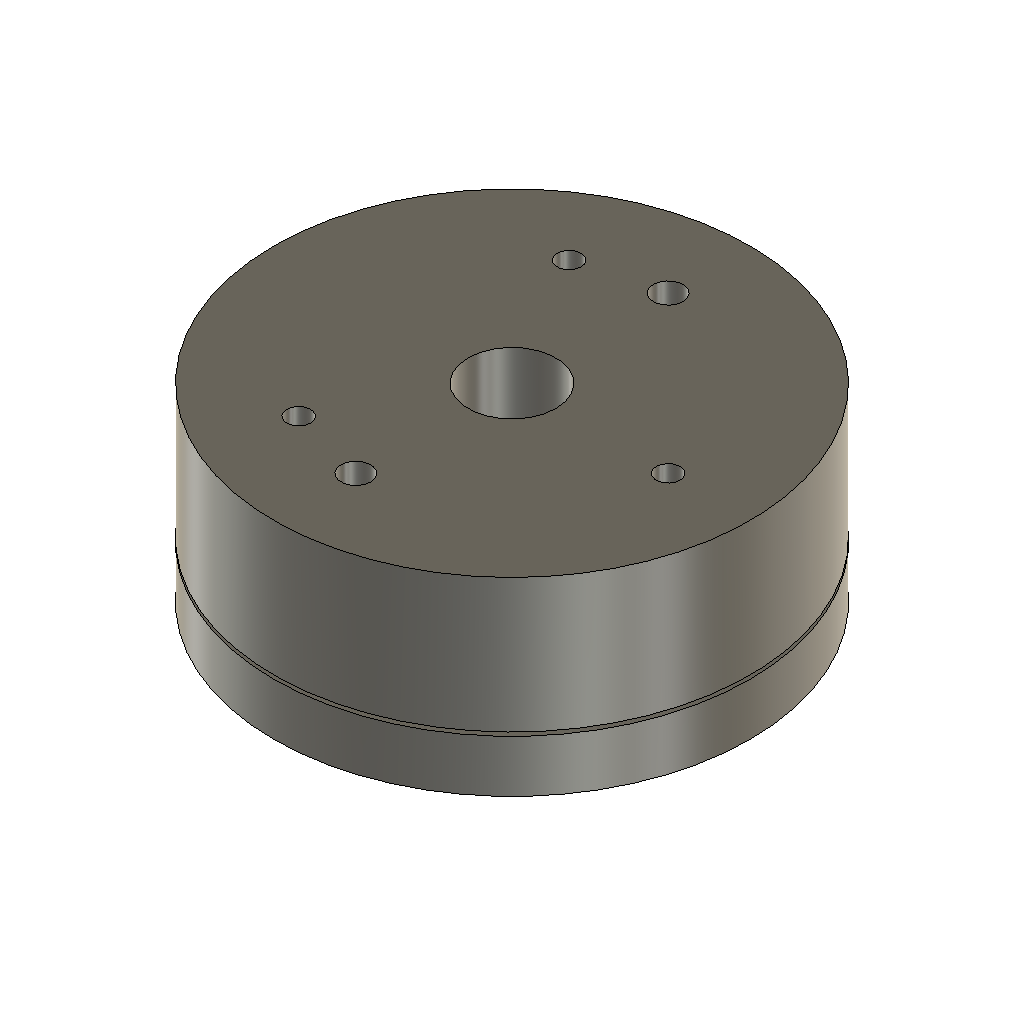
SmartKnob Enclosure (Autodesk Fusion 360 archive; units mm, degrees)
design "BLDCMotor v1"
Autodesk Fusion 360 part; units mm, degrees
sketch "BottomStator" plane through (0, 0, 0) normal (0, 0, 1) x (1, 0, 0)
  circle A0 centre (10.2509, 0) radius 0.8
  circle A1 centre (-5.1254, 8.8775) radius 0.8
  line L0 (-12.3, 4) -> (-9, 4)
  line L1 (-12.3, -4) -> (-12.3, 4)
  circle A2 centre (0, 0) radius 5.75
  line L2 (0, 0) -> (-5.1254, -8.8775) construction
  line L3 (-9, 4) -> (-9, -4)
  line L4 (0, 0) -> (-5.1254, 8.8775) construction
  circle A3 centre (-5.1254, -8.8775) radius 0.8
  line L5 (10.2509, 0) -> (0, 0) construction
  line L6 (-5.1254, -8.8775) -> (-5.1254, 8.8775) construction
  circle A4 centre (0, 0) radius 16
  line L7 (10.2509, 0) -> (-5.1254, -8.8775) construction
  line L8 (-5.1254, 8.8775) -> (10.2509, 0) construction
  circle A5 centre (0, 0) radius 2.95
  line L9 (-9, -4) -> (-12.3, -4)
  point P0 (-9, 0)
  dimension "d1" = 1.6
  dimension "d2" = 1.6
  dimension "d3" = 1.6
  dimension "d4" = 17.755
  dimension "d5" = 11.5
  dimension "d11" = 32
  dimension "d21" = 8
  dimension "d22" = 9
  dimension "d23" = 5.9
  dimension "d18" = 3.3
  dimension "d36" = 10.2509
  constraint coincident A0.centre L5.start
  constraint coincident L2.end A3.centre
  constraint coincident A1.centre L4.end
  constraint coincident A2.centre L2.start
  constraint equal L2 L5
  constraint equal L2 L4
  constraint equal L6 L7
  constraint equal L7 L8
  constraint horizontal L5
  constraint horizontal L0
  constraint vertical L3
  constraint horizontal L9
  constraint vertical L1
  constraint midpoint P0 L3
  constraint coincident P0 L5
  measures "d1" diameter of A0
  measures "d2" diameter of A3
  measures "d3" diameter of A1
  measures "d4" distance of A0.centre L2.end
  measures "d5" diameter of A2
  measures "d11" diameter of A4
  measures "d21" distance of L0.start L1.start
  measures "d22" distance of P0 A2.centre
  measures "d23" diameter of A5
  measures "d18" distance of L0.start L0.end
  measures "d36" distance of A0.centre A2.centre
sketch "TopRotor" plane through (0, 0, 0) normal (0, 0, 1) x (1, 0, 0)
  line L0 (-5.25, 9.0933) -> (10.5, 0) construction
  line L1 (10.5, 0) -> (-5.25, -9.0933) construction
  line L2 (-5.25, -9.0933) -> (-5.25, 9.0933) construction
  line L3 (-5.25, 9.0933) -> (0, 0) construction
  line L4 (0, 0) -> (10.5, 0) construction
  line L5 (0, 0) -> (-5.25, -9.0933) construction
  circle A0 centre (-5.25, 9.0933) radius 0.8
  circle A1 centre (10.5, 0) radius 0.8
  circle A2 centre (-5.25, -9.0933) radius 0.8
  line L6 (0, 10.5) -> (0, -10.5) construction
  circle A3 centre (0, 10.5) radius 1
  circle A4 centre (0, -10.5) radius 1
  circle A5 centre (0, 0) radius 16
  circle A6 centre (0, 0) radius 5.75
  circle A7 centre (0, 0) radius 2.95
  dimension "d32" = 10.5
  dimension "d33" = 1.6
  dimension "d34" = 1.6
  dimension "d35" = 1.6
  dimension "d37" = 18.1865
  dimension "d38" = 21
  dimension "d39" = 2
  dimension "d40" = 2
  dimension "d43" = 32
  dimension "d45" = 11.5
  dimension "d53" = 5.9
  constraint vertical L2
  constraint equal L0 L2
  constraint equal L0 L1
  constraint equal L3 L4
  constraint equal L4 L5
  constraint coincident L3.end L4.start
  constraint coincident L0.start L2.end
  constraint coincident L0.end L1.start
  constraint coincident L1.end L2.start
  constraint vertical L6
  constraint midpoint L6 L3.end
  constraint coincident L6.start A3.centre
  constraint coincident L6.end A4.centre
  constraint concentric A5 A6
  constraint concentric A6 A7
  measures "d32" distance of L0.end L3.end
  measures "d33" diameter of A0
  measures "d34" diameter of A1
  measures "d35" diameter of A2
  measures "d37" distance of L0.start L0.end
  measures "d38" distance of L6.start L6.end
  measures "d39" diameter of A3
  measures "d40" diameter of A4
  measures "d43" diameter of A5
  measures "d45" diameter of A6
  measures "d53" diameter of A7
extrude "Extrude1" add sketch "BottomStator" along normal blind 3.5 contours A4 makes body 1 in component "Stator"
extrude "Extrude1'" add sketch "TopRotor" against normal blind 9 from surface at 12.75 separate body contours A5 makes body 2 in component "Rotor"
extrude "Extrude2" add sketch "TopRotor" against normal blind 15 from surface at 12.75 contours A6 bodies 2 in component "Rotor"
component "Stator" placed x (1, 0, 0) y (0, 1, 0) z (0, 0, 1) at (0, 0, 0)
component "Rotor" placed x (1, 0, 0) y (0, 1, 0) z (0, 0, 1) at (0, 0, 0)
equation "d2 = d1"
equation "d3 = d1"
equation "d5 = magnet_diameter"
equation "d11 = diameter"
equation "d23 = inner_diameter"
equation "d28 = 3 mm"
equation "d29 = d28"
equation "d30 = d28"
equation "d32 = ( 21 / 2 ) * 1 mm"
equation "d34 = d33"
equation "d35 = d33"
equation "d40 = d39"
equation "height = 12.75 mm"
equation "diameter = 32 mm"
equation "d43 = diameter"
equation "magnet_diameter = 11.5 mm"
equation "d45 = magnet_diameter"
equation "d46 = height"
equation "d49 = height"
equation "inner_diameter = 5.9 mm"
equation "d53 = inner_diameter"

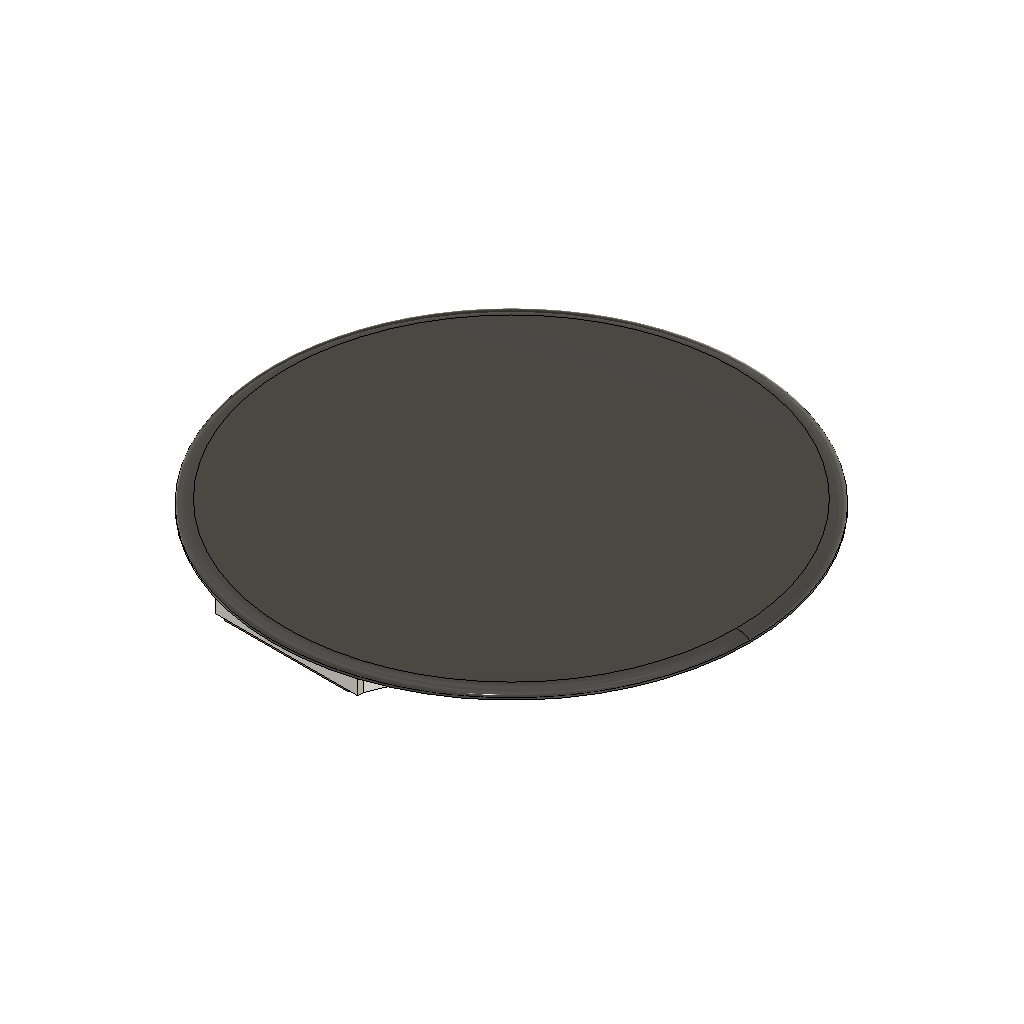
design "Display"
Autodesk Fusion 360 part; units mm, degrees
sketch "Sketch1" plane through (0, 0, 0) normal (0, 0, 1) x (1, 0, 0)
  circle A0 centre (0, 0) radius 16.2
  circle A1 centre (0, 0) radius 17.37 construction
  circle A2 centre (0, 0) radius 17.6 construction
  circle A3 centre (0, 0) radius 17.8
  line L0 (0, 0) -> (0, -34.4204) construction
  line L1 (-6.6, -20.3) -> (6.6, -20.3)
  line L2 (8.5, -15.6394) -> (-8.5, -15.6394) construction
  line L3 (6.6, -20.3) -> (8.5, -15.6394)
  line L4 (-6.6, -20.3) -> (-8.5, -15.6394)
  line L5 (-6.6, -20.3) -> (-6.6, -20.8)
  line L6 (-6.6, -20.8) -> (6.6, -20.8)
  line L7 (6.6, -20.8) -> (6.6, -20.3)
  circle A4 centre (0, 0) radius 22.5 construction
  line L8 (-5.7, -20.8) -> (5.7, -20.8)
  line L9 (5.7, -20.8) -> (5.7, -10.06)
  line L10 (5.7, -10.06) -> (-5.7, -10.06)
  line L11 (-5.7, -10.06) -> (-5.7, -20.8)
  point P0 (0, -20.3)
  dimension "d1" = 32.4
  dimension "d2" = 34.74
  dimension "d3" = 35.2
  dimension "d4" = 35.6
  dimension "d5" = 13.2
  dimension "d6" = 20.3
  dimension "d7" = 17
  dimension "d8" = 0.5
  dimension "d9" = 21.822
  dimension "d10" = 45
  dimension "d11" = 0.678
  dimension "d24" = 11.4
  dimension "d25" = 10.24
  constraint coincident A0.centre A1.centre
  constraint concentric A0 A1
  constraint concentric A1 A2
  constraint concentric A0 A3
  constraint vertical L0
  constraint horizontal L1
  constraint midpoint L1 P0
  constraint coincident L0 P0
  constraint coincident A3 L2.start
  constraint coincident A3 L2.end
  constraint horizontal L2
  constraint perpendicular L1 L5
  constraint perpendicular L5 L6
  constraint vertical L7
  constraint concentric A0 A4
  constraint horizontal L8
  constraint vertical L9
  constraint horizontal L10
  constraint vertical L11
  constraint coincident L6 L8.start
  constraint midpoint L6 L8
  measures "d1" diameter of A0
  measures "d2" diameter of A1
  measures "d3" diameter of A2
  measures "d4" diameter of A3
  measures "d5" distance of L1.start L1.end
  measures "d6" distance of A0.centre L1
  measures "d7" distance of L2.start L2.end
  measures "d8" distance of L1 L6
  measures "d9" distance of A0.centre L6.end
  measures "d10" diameter of A4
  measures "d11" distance of L6.end A4
  measures "d24" distance of L8.start L8.end
  measures "d25" distance of L1 L10
extrude "Extrude2" add sketch "Sketch1" along normal blind 1.5 makes body 1
extrude "Extrude5" add sketch "Sketch1" against normal blind 0.13 separate body contours A0 L9 L10 L11 | A0 A3 L9 L11 | A3 L1 L9 L11 | L1 L6 L8 L9 L11 picked at (0.388, -12.0927) picked at (-4.9559, -15.9504) makes body 2
sketch "Sketch3" plane through (0, 0, 1.5) normal (0, 0, 1) x (-1, 0, 0)
  line L0 (6.6, 20.3) -> (6.6, 20.8)
  line L1 (6.6, 20.8) -> (-6.6, 20.8)
  line L2 (-6.6, 20.8) -> (-6.6, 20.3)
  line L3 (-6.6, 20.3) -> (-8.5, 15.6394)
  arc A0 (-8.5, 15.6394) -> (8.5, 15.6394) centre (0, 0) ccw
  line L4 (8.5, 15.6394) -> (6.6, 20.3)
  circle A1 centre (0, 0) radius 22
  dimension "d28" = 44
  constraint coincident A0.centre A1.centre
  measures "d28" diameter of A1
extrude "Extrude6" add sketch "Sketch3" along normal blind 0.6 contours L0 L1 L2 L3 A0 L4 | A1 bodies 1
fillet "Fillet1" offset 1.2 second offset 0.4 1 edges at (20.5112, 7.9555, 2.1) measured on face at (-5.8152, 3.0625, 2.1) on bodies 1
equation "d6 = 38.1 mm - d4 / 2"
named bodies: "LCd", "FPC"
